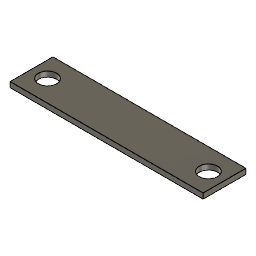
Wireless charger circuit mount (Autodesk Fusion 360 design; units mm, degrees)
Autodesk Fusion 360 part; units mm, degrees
sketch "Sketch1" plane through (0, 0, 0) normal (0, 0, 1) x (1, 0, 0)
  line L0 (0, 0) -> (36, 0)
  line L1 (36, 0) -> (36, 8)
  line L2 (36, 8) -> (0, 8)
  line L3 (0, 8) -> (0, 0)
  dimension "d1" = 36
  dimension "d2" = 8
  constraint horizontal L0
  constraint vertical L1
  constraint horizontal L2
  constraint vertical L3
  constraint coincident L0.start L3.end
  measures "d1" distance of L0.start L0.end
  measures "d2" distance of L0.start L2.end
extrude "Extrude1" add sketch "Sketch1" along normal blind 1
sketch "Sketch2" plane through (0, 0, 1) normal (0, 0, 1) x (-1, 0, 0)
  line L0 (0, -8) -> (0, 0)
  line L1 (0, 0) -> (-36, 0)
  line L2 (-36, 0) -> (-36, -8)
  line L3 (-36, -8) -> (0, -8)
  line L4 (-3, -4) -> (-33, -4)
  circle A0 centre (-3, -4) radius 1.7
  circle A1 centre (-33, -4) radius 1.7
  point P0 (-18, -4)
  dimension "d5" = 30
  dimension "d6" = 3.4
  dimension "d7" = 3.4
  constraint midpoint L4 P0
  constraint perpendicular L0 L4
  constraint coincident L4.start A0.centre
  constraint coincident L4.end A1.centre
  measures "d5" distance of L4.start L4.end
  measures "d6" diameter of A0
  measures "d7" diameter of A1
extrude "Extrude2" cut sketch "Sketch2" against normal blind 1 contours A0 | A1
